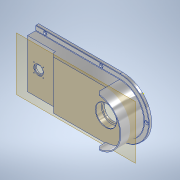
# Autodesk Inventor part: 1.5_1_MainBase
Saved by Autodesk Inventor 2021 (Build 250183000, 183)
## iProperties
Created: 2025-11-20
Part Number: 1.5_1_MainBase
Material: Aluminum 6061
Document SubType Name: Modeling
Designer: Admin
Density: 2.7 g/cm^3
Appearance: Aluminum - Flat
Mass: 17740.2 g
Surface Area: 5498.56 cm^2
Volume: 6570.43 cm^3
Author: Admin
Autodesk Inventor part; units mm, degrees
ref_plane "YZ Plane" through (0, 0, 0) normal (1, 0, 0) x (0, 1, 0)
ref_plane "XZ Plane" through (0, 0, 0) normal (0, 1, 0) x (-1, 0, 0)
sketch "Sketch1" plane through (0, 0, 0) normal (0, 0, 1) x (1, 0, 0)
  circle A0 centre (0, 0) radius 130
  line L0 (0, 130) -> (-450, 130)
  line L1 (-450, 130) -> (-450, -130)
  line L2 (-450, -130) -> (0, -130)
  dimension "d0" = 260
  dimension "d1" = 450
  constraints: 6 end point, 2 perpendicular, 2 point on circle, 2 tangent, 1 centre point, 1 coincident, 1 horizontal
  measures "d0" diameter of A0
  measures "d1" distance from line of point (0, 0) L1
extrude "Extrusion1" add sketch "Sketch1" along normal blind 200
sketch "Sketch2" plane through (0, 0, 0) normal (0, 0, -1) x (-1, 0, 0)
  line L0 (450, -130) -> (0, -130) projected
  arc A0 (0, 130) -> (0, -130) centre (0, 0) ccw projected
  line L1 (0, 130) -> (450, 130) projected
  line L2 (450, -100) -> (0, -100)
  arc A1 (0, 100) -> (0, -100) centre (0, 0) ccw
  line L3 (0, 100) -> (450, 100)
  line L4 (450, -100) -> (450, 100)
  line L5 (450, 130) -> (450, -130) projected
  dimension "d4" = 30
  constraints: 6 end point, 2 point on circle, 1 centre point, 1 collinear, 1 perpendicular, 2 other
  measures "d4" distance between parallel lines of L0 L2
extrude "Extrusion2" cut sketch "Sketch2" against normal blind 160 contours L2 A1 L3 L4
sketch "Sketch3" plane through (0, 0, 0) normal (0, 1, 0) x (-1, 0, 0)
  point P0 (0, 0)
sketch "Sketch4" plane through (0, 0, 200) normal (0, 0, 1) x (1, 0, 0)
  circle A0 centre (0, 0) radius 125
  line L0 (0, 125) -> (-60, 125)
  line L1 (-60, 125) -> (-60, 130)
  line L2 (0, 130) -> (-450, 130) projected
  line L3 (0, 182) -> (0, -182) projected
  arc A1 (0, -130) -> (0, 130) centre (0, 0) ccw projected
  line L4 (0, 130) -> (-450, 130) projected
  line L5 (0, -125) -> (-60, -125)
  line L6 (-60, -125) -> (-60, -130)
  line L7 (-450, -130) -> (0, -130) projected
  dimension "d7" = 250
  dimension "d8" = 60
  dimension "d9" = 60
  constraints: 8 end point, 3 point on line, 2 horizontal, 2 perpendicular, 2 point on circle, 2 tangent, 1 centre point, 1 coincident
  measures "d7" diameter of A0
  measures "d8" distance between parallel lines of L1 L3
  measures "d9" distance of L7.end L6.end
extrude "Extrusion3" add sketch "Sketch4" along normal blind 50 contours A0 L3 A1
sketch "Sketch5" plane through (0, 0, 0) normal (0, 1, 0) x (-1, 0, 0)
  line L0 (0, 200) -> (-125, 200) projected
  line L1 (-55, 200) -> (-55, 170)
  line L2 (-55, 170) -> (-47, 170)
  line L3 (-47, 170) -> (-47, 160)
  line L4 (0, 160) -> (-100, 160) projected
  line L5 (0, 0) -> (0, 200) projected
  line L6 (0, 160) -> (0, 200)
  line L7 (0, 200) -> (-55, 200)
  line L8 (-47, 160) -> (0, 160)
  line L9 (0, -40) -> (0, 240) projected
  dimension "d12" = 55
  dimension "d14" = 8
  dimension "d15" = 30
  constraints: 12 end point, 3 perpendicular, 2 point on line, 1 collinear, 1 parallel, 1 vertical
  measures "d12" distance between parallel lines of L5 L1
  measures "d14" distance of L1.end L2.end
  measures "d15" distance of L1.start L1.end
revolve "Revolution1" cut sketch "Sketch5" angle 360 about axis through (0, 0, -10) along (0, 0, 1)
ref_plane "Work Plane1" through (0, 0, 200) normal (0, 0, 1) x (1, 0, 0)
sketch "Sketch10" plane through (0, 0, 0) normal (0, 1, 0) x (-1, 0, 0)
  line L0 (0, 0) -> (450, 0) projected
  line L1 (-130, 0) -> (-130, 250) projected
  line L2 (450, 0) -> (-130, 0)
  line L3 (-130, 0) -> (-130, 110)
  line L4 (-130, 110) -> (450, 110)
  line L5 (450, 110) -> (450, 0)
  line L6 (0, 160) -> (450, 160) projected
  point P0 (150, 150)
  dimension "d40" = 110
  constraints: 8 end point, 2 parallel, 1 horizontal, 1 perpendicular, 1 point on line, 1 other
  measures "d40" distance between parallel lines of L0 L4
extrude "Extrusion6" cut sketch "Sketch10" along normal through all both and the other way through all
sketch "Sketch11" plane through (0, 130, 110) normal (0, 0, -1) x (-1, 0, 0)
  line L0 (450, -260) -> (0, -260) projected
  arc A0 (0, 0) -> (0, -260) centre (0, -130) ccw projected
  line L1 (0, 0) -> (450, 0) projected
  line L2 (450, -285) -> (0, -285)
  arc A1 (0, 25) -> (0, -285) centre (0, -130) ccw
  line L3 (0, 25) -> (450, 25)
  line L4 (450, -260) -> (0, -260) projected
  line L5 (450, -285) -> (450, -260)
  line L6 (450, 0) -> (450, 25)
  point P0 (0, -130)
  dimension "d41" = 25
  constraints: 8 end point, 2 point on circle, 2 vertical, 1 centre point, 2 other
  measures "d41" distance between parallel lines of L0 L2
extrude "Extrusion7" add sketch "Sketch11" against normal blind 15
sketch "Sketch12" plane through (0, 0, 200) normal (0, 0, 1) x (1, 0, 0)
  line L0 (0, 130) -> (-450, 130) projected
  line L1 (-450, 130) -> (-300, 130)
  line L2 (-300, 130) -> (-300, -133.0816)
  line L3 (-300, -133.0816) -> (-450, -133.0816)
  line L4 (-450, -133.0816) -> (-450, 130)
  point P0 (0, 0)
  dimension "d44" = 150
  constraints: 8 end point, 2 parallel, 1 horizontal, 1 perpendicular
  measures "d44" distance between parallel lines of L4 L2
extrude "Extrusion8" cut sketch "Sketch12" against normal blind 30
sketch "Sketch13" plane through (0, 0, 170) normal (0, 0, 1) x (1, 0, 0)
  circle A0 centre (-390, 0) radius 35
  line L0 (-450, -130) -> (-450, 130) projected
  line L1 (-414.7487, 24.7487) -> (-365.2513, 24.7487)
  line L2 (-365.2513, 24.7487) -> (-365.2513, -24.7487)
  line L3 (-365.2513, -24.7487) -> (-414.7487, -24.7487)
  line L4 (-414.7487, -24.7487) -> (-414.7487, 24.7487)
  line L5 (-571, 0) -> (276, 0) projected
  point P0 (0, 0)
  point P1 (-365.2513, -24.7487)
  dimension "d47" = 70
  dimension "d48" = 60
  constraints: 8 end point, 4 coincident, 3 point on circle, 2 parallel, 2 perpendicular, 1 centre point, 1 horizontal, 1 point on line
  measures "d47" diameter of A0
  measures "d48" distance from line of L0 A0.centre
hole "Hole2" at (-414.7487, -24.7487, 170) at (-414.7487, 24.7487, 170) at (-365.2513, 24.7487, 170) at (-365.2513, -24.7487, 170) direction (0, 0, -1) diameter 4.134 end through all thread size "M5x0.8" class "6H" standard "ISO Metric profile"
sketch "Sketch14" plane through (0, 0, 0) normal (0, 1, 0) x (-1, 0, 0)
  line L0 (450, 170) -> (300, 170) projected
  line L1 (416, 170) -> (416, 166.8)
  line L2 (416, 166.8) -> (411, 166.8)
  line L3 (411, 166.8) -> (411, 160)
  line L4 (411, 160) -> (390, 160)
  line L5 (0, 160) -> (450, 160) projected
  line L6 (390, 170) -> (416, 170)
  line L7 (390, 160) -> (390, 170)
  line L8 (450, 125) -> (450, 170) projected
  point P0 (0, 0)
  dimension "d56" = 26
  dimension "d57" = 3.2
  dimension "d58" = 5
  dimension "d59" = 60
  constraints: 12 end point, 3 perpendicular, 2 point on line, 1 collinear, 1 parallel, 1 vertical
  measures "d56" distance between parallel lines of L7 L1
  measures "d57" distance of L1.start L1.end
  measures "d58" distance of L1.end L2.end
  measures "d59" distance between parallel lines of L8 L7
revolve "Revolution3" cut sketch "Sketch14" angle 360 about axis through (-390, 0, 160) along (0, 0, 1) contours L1 L2 L3 L4 L7 L0
sketch "Sketch15" plane through (0, 130, 125) normal (0, 0, 1) x (1, 0, 0)
  line L0 (-450, -285) -> (0, -285) projected
  line L1 (0, 25) -> (-450, 25) projected
  arc A0 (0, -285) -> (0, 25) centre (0, -130) ccw projected
  line L2 (-450, -272.5) -> (0, -272.5)
  arc A1 (0, -272.5) -> (0, 12.5) centre (0, -130) ccw
  line L3 (0, 12.5) -> (-450, 12.5)
  line L4 (-450, -260) -> (-450, 0) projected
  line L5 (-100, 12.5) -> (-100, -389.5958)
  line L6 (-400, -272.5) -> (-400, 97.8631)
  line L7 (-571, -130) -> (276, -130) projected
  point P0 (0, -130)
  point P1 (-100, -272.5)
  point P2 (-400, 12.5)
  point P3 (142.5, -130)
  dimension "d61" = 12.5
  dimension "d62" = 50
  dimension "d63" = 350
  constraints: 8 end point, 7 point on line, 3 point on circle, 2 vertical, 1 centre point, 2 other
  measures "d61" distance between parallel lines of L0 L2
  measures "d62" distance from line of L4 L6.start
  measures "d63" distance from line of L4 L5.start
hole "Hole3" at (142.5, 0, 125) at (-100, -142.5, 125) at (-400, -142.5, 125) at (-400, 142.5, 125) at (-100, 142.5, 125) direction (0, 0, -1) diameter 9 end through all counterbore diameter 20 counterbore depth 6.3
fillet "Fillet1" radius 2 3 edges at (-225, 130, 125) (-225, -130, 125) (130, 0, 125)
chamfer "Chamfer2" distance 2 angle 45 3 edges at (-225, -155, 125) (155, 0, 125) (-225, 155, 125)
chamfer "Chamfer3" distance 15 angle 45 2 edges at (0, -127.5, 250) (0, 127.5, 250)
chamfer "Chamfer4" distance 20 angle 45 1 edges at (-300, 0, 200)
chamfer "Chamfer5" distance 2 angle 45 1 edges at (-55, 0, 200)
body "Solid1"
